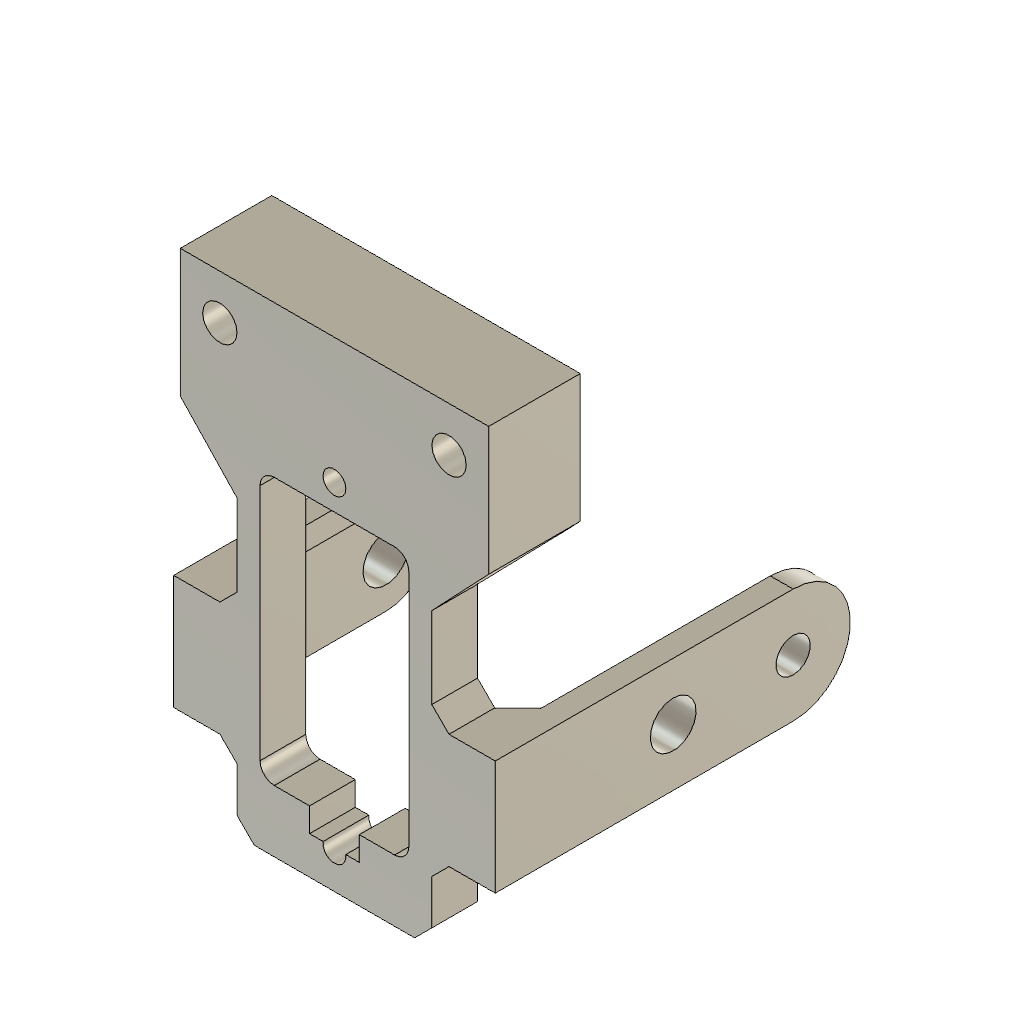
Sub Base native (Autodesk Fusion 360 design; units mm, degrees)
part number: 2026-10-13-22-11-32-808
Autodesk Fusion 360 part; units mm, degrees
ref_plane "WorkPlane1" through (0, -13.5322, 0) normal (0, 1, 0) x (0, 0, 1)
sketch "Back plate" plane through (0, -13.5322, 0) normal (0, 1, 0) x (1, 0, 0)
  line L0 (50.9682, -30.0122) -> (24.0314, -30.0122)
  line L1 (24.0314, -30.0122) -> (24.0314, -18.8374)
  line L2 (24.0314, -18.8374) -> (28.9998, -13.5996)
  line L3 (28.9998, -13.5996) -> (28.9998, -6.5)
  line L4 (28.9998, -6.5) -> (27.4998, -5)
  line L5 (27.4998, -5) -> (23.4588, -5)
  line L6 (23.4588, -5) -> (23.4588, 5)
  line L7 (23.4588, 5) -> (27.4998, 5)
  line L8 (27.4998, 5) -> (28.9998, 6.5)
  line L9 (28.9998, 6.5) -> (28.9998, 10.4007)
  line L10 (28.9998, 10.4007) -> (30.4998, 11.9007)
  line L11 (30.4998, 11.9007) -> (44.4998, 11.9007)
  line L12 (44.4998, 11.9007) -> (45.9998, 10.4007)
  line L13 (45.9998, 10.4007) -> (45.9998, 6.5)
  line L14 (45.9998, 6.5) -> (47.4998, 5)
  line L15 (47.4998, 5) -> (51.5407, 5)
  line L16 (51.5407, 5) -> (51.5407, -5)
  line L17 (51.5407, -5) -> (47.4998, -5)
  line L18 (47.4998, -5) -> (45.9998, -6.5)
  line L19 (45.9998, -6.5) -> (45.9998, -13.5996)
  line L20 (45.9998, -13.5996) -> (50.9682, -18.8374)
  line L21 (50.9682, -18.8374) -> (50.9682, -30.0122)
  dimension "d59" = 50.9682
  dimension "d60" = 30.0122
  dimension "d61" = 24.0314
  dimension "d62" = 18.8374
  dimension "d63" = 28.9998
  dimension "d64" = 13.5996
  dimension "d65" = 6.5
  dimension "d66" = 27.4998
  dimension "d67" = 5
  dimension "d68" = 23.4588
  dimension "d69" = 5
  dimension "d70" = 27.4998
  dimension "d71" = 28.9998
  dimension "d72" = 6.5
  dimension "d73" = 10.4007
  dimension "d74" = 30.4998
  dimension "d75" = 11.9007
  dimension "d76" = 44.4998
  dimension "d77" = 45.9998
  dimension "d78" = 10.4007
  dimension "d79" = 6.5
  dimension "d80" = 47.4998
  dimension "d81" = 5
  dimension "d82" = 51.5407
  dimension "d83" = 5
  dimension "d84" = 47.4998
  dimension "d85" = 45.9998
  dimension "d86" = 6.5
  dimension "d87" = 13.5996
  dimension "d88" = 18.8374
  constraint horizontal L0
  constraint vertical L1
  constraint vertical L3
  constraint horizontal L5
  constraint vertical L6
  constraint horizontal L7
  constraint vertical L9
  constraint horizontal L11
  constraint vertical L13
  constraint horizontal L15
  constraint vertical L16
  constraint horizontal L17
  constraint vertical L19
  constraint vertical L21
  measures "d59" horizontal distance of origin L0.start
  measures "d60" vertical distance of origin L0.start
  measures "d61" horizontal distance of origin L0.end
  measures "d62" vertical distance of origin L1.end
  measures "d63" horizontal distance of origin L2.end
  measures "d64" vertical distance of origin L2.end
  measures "d65" vertical distance of origin L3.end
  measures "d66" horizontal distance of origin L4.end
  measures "d67" vertical distance of origin L4.end
  measures "d68" horizontal distance of origin L5.end
  measures "d69" vertical distance of origin L6.end
  measures "d70" horizontal distance of origin L7.end
  measures "d71" horizontal distance of origin L8.end
  measures "d72" vertical distance of origin L8.end
  measures "d73" vertical distance of origin L9.end
  measures "d74" horizontal distance of origin L10.end
  measures "d75" vertical distance of origin L10.end
  measures "d76" horizontal distance of origin L11.end
  measures "d77" horizontal distance of origin L12.end
  measures "d78" vertical distance of origin L12.end
  measures "d79" vertical distance of origin L13.end
  measures "d80" horizontal distance of origin L14.end
  measures "d81" vertical distance of origin L14.end
  measures "d82" horizontal distance of origin L15.end
  measures "d83" vertical distance of origin L16.end
  measures "d84" horizontal distance of origin L17.end
  measures "d85" horizontal distance of origin L18.end
  measures "d86" vertical distance of origin L18.end
  measures "d87" vertical distance of origin L19.end
  measures "d88" vertical distance of origin L20.end
extrude "Back plate (1)" add sketch "Back plate" along normal mid plane 4
ref_plane "WorkPlane2" through (0, -9.5322, 0) normal (0, 1, 0) x (0, 0, 1)
sketch "Top block" plane through (0, -9.5322, 0) normal (0, 1, 0) x (1, 0, 0)
  line L0 (50.9682, -30.0122) -> (24.0314, -30.0122)
  line L1 (24.0314, -30.0122) -> (24.0314, -18.8374)
  line L2 (24.0314, -18.8374) -> (28.9998, -13.5996)
  line L3 (28.9998, -13.5996) -> (28.9998, -22.1993)
  line L4 (28.9998, -22.1993) -> (45.9998, -22.1993)
  line L5 (45.9998, -22.1993) -> (45.9998, -13.5996)
  line L6 (45.9998, -13.5996) -> (50.9682, -18.8374)
  line L7 (50.9682, -18.8374) -> (50.9682, -30.0122)
  dimension "d89" = 50.9682
  dimension "d90" = 30.0122
  dimension "d91" = 24.0314
  dimension "d92" = 18.8374
  dimension "d93" = 28.9998
  dimension "d94" = 13.5996
  dimension "d95" = 22.1993
  dimension "d96" = 45.9998
  dimension "d97" = 13.5996
  dimension "d98" = 18.8374
  constraint horizontal L0
  constraint vertical L1
  constraint vertical L3
  constraint horizontal L4
  constraint vertical L5
  constraint vertical L7
  measures "d89" horizontal distance of origin L0.start
  measures "d90" vertical distance of origin L0.start
  measures "d91" horizontal distance of origin L0.end
  measures "d92" vertical distance of origin L1.end
  measures "d93" horizontal distance of origin L2.end
  measures "d94" vertical distance of origin L2.end
  measures "d95" vertical distance of origin L3.end
  measures "d96" horizontal distance of origin L4.end
  measures "d97" vertical distance of origin L5.end
  measures "d98" vertical distance of origin L6.end
extrude "Top block (1)" add sketch "Top block" along normal mid plane 4
ref_plane "WorkPlane3" through (0, 0, 17.8995) normal (0, 0, 1) x (1, 0, 0)
sketch "Gusset taper L" plane through (0, 0, 17.8995) normal (0, 0, 1) x (1, 0, 0)
  line L0 (28.9998, -11.5322) -> (24.9998, -7.5322)
  line L1 (24.9998, -7.5322) -> (28.9998, -7.5322)
  line L2 (28.9998, -7.5322) -> (28.9998, -11.5322)
  dimension "d99" = 28.9998
  dimension "d100" = 11.5322
  dimension "d101" = 24.9998
  dimension "d102" = 7.5322
  constraint horizontal L1
  constraint vertical L2
  measures "d99" horizontal distance of origin L0.start
  measures "d100" vertical distance of origin L0.start
  measures "d101" horizontal distance of origin L0.end
  measures "d102" vertical distance of origin L0.end
extrude "Gusset taper L (1)" cut sketch "Gusset taper L" along normal mid plane 8.5997
ref_plane "WorkPlane4" through (0, 0, 17.8995) normal (0, 0, 1) x (1, 0, 0)
sketch "Gusset taper R" plane through (0, 0, 17.8995) normal (0, 0, 1) x (1, 0, 0)
  line L0 (45.9998, -11.5322) -> (45.9998, -7.5322)
  line L1 (45.9998, -7.5322) -> (49.9998, -7.5322)
  line L2 (49.9998, -7.5322) -> (45.9998, -11.5322)
  dimension "d103" = 45.9998
  dimension "d104" = 11.5322
  dimension "d105" = 7.5322
  dimension "d106" = 49.9998
  constraint vertical L0
  constraint horizontal L1
  measures "d103" horizontal distance of origin L0.start
  measures "d104" vertical distance of origin L0.start
  measures "d105" vertical distance of origin L0.end
  measures "d106" horizontal distance of origin L1.end
extrude "Gusset taper R (1)" cut sketch "Gusset taper R" along normal mid plane 8.5997
ref_plane "WorkPlane5" through (24.9588, 0, 0) normal (1, 0, 0) x (0, 1, 0)
sketch "Arm L" plane through (24.9588, 0, 0) normal (1, 0, 0) x (0, 0, -1)
  line L0 (-5, -15.5322) -> (-5, 0)
  arc A0 (5, 0) -> (-5, 0) centre (0, 0) ccw
  line L1 (5, 0) -> (5, -15.5322)
  line L2 (5, -15.5322) -> (-5, -15.5322)
  dimension "d107" = 5
  dimension "d108" = 15.5322
  constraint vertical L0
  constraint vertical L1
  constraint horizontal L2
  constraint tangent L0 A0
  constraint tangent A0 L1
  constraint coincident A0.centre origin
  measures "d107" radius of A0
  measures "d108" vertical distance of A0.centre L0.start
extrude "Arm L (1)" add sketch "Arm L" along normal mid plane 3
ref_plane "WorkPlane6" through (50.0407, 0, 0) normal (1, 0, 0) x (0, 1, 0)
sketch "Arm R" plane through (50.0407, 0, 0) normal (1, 0, 0) x (0, 0, -1)
  line L0 (-5, -15.5322) -> (-5, 10.47)
  arc A0 (5, 10.47) -> (-5, 10.47) centre (0, 10.47) ccw
  line L1 (5, 10.47) -> (5, -15.5322)
  line L2 (5, -15.5322) -> (-5, -15.5322)
  dimension "d109" = 5
  dimension "d110" = 10.47
  dimension "d111" = 15.5322
  constraint vertical L0
  constraint vertical L1
  constraint horizontal L2
  constraint tangent L0 A0
  constraint tangent A0 L1
  constraint vertical origin A0.centre
  measures "d109" radius of A0
  measures "d110" vertical distance of origin A0.centre
  measures "d111" vertical distance of origin L0.start
extrude "Arm R (1)" add sketch "Arm R" along normal mid plane 3
chamfer "Arm L chamfer" distance 1 angle 45 3 edges at (26.4588, -5.7661, -5) (26.4588, 5, 0) (26.4588, -5.7661, 5) tangent chain off
chamfer "Arm R chamfer" distance 1 angle 45 3 edges at (48.5407, -0.5311, 5) (48.5407, 15.47, 0) (48.5407, -0.5311, -5) tangent chain off
sketch "Arm root L" plane through (0, 0, 0) normal (0, 0, 1) x (1, 0, 0)
  line L0 (27.4588, -11.5322) -> (25.4588, -9.5322)
  line L1 (25.4588, -9.5322) -> (25.4588, -11.5322)
  line L2 (25.4588, -11.5322) -> (27.4588, -11.5322)
  dimension "d112" = 27.4588
  dimension "d113" = 11.5322
  dimension "d114" = 25.4588
  dimension "d115" = 9.5322
  constraint vertical L1
  constraint horizontal L2
  measures "d112" horizontal distance of origin L0.start
  measures "d113" vertical distance of origin L0.start
  measures "d114" horizontal distance of origin L0.end
  measures "d115" vertical distance of origin L0.end
extrude "Arm root L (1)" add sketch "Arm root L" along normal mid plane 10
sketch "Arm root R" plane through (0, 0, 0) normal (0, 0, 1) x (1, 0, 0)
  line L0 (47.5407, -11.5322) -> (49.5407, -11.5322)
  line L1 (49.5407, -11.5322) -> (49.5407, -9.5322)
  line L2 (49.5407, -9.5322) -> (47.5407, -11.5322)
  dimension "d116" = 47.5407
  dimension "d117" = 11.5322
  dimension "d118" = 49.5407
  dimension "d119" = 9.5322
  constraint horizontal L0
  constraint vertical L1
  measures "d116" horizontal distance of origin L0.start
  measures "d117" vertical distance of origin L0.start
  measures "d118" horizontal distance of origin L0.end
  measures "d119" vertical distance of origin L1.end
extrude "Arm root R (1)" add sketch "Arm root R" along normal mid plane 10
ref_plane "WorkPlane7" through (24.9588, 0, 0) normal (1, 0, 0) x (0, 1, 0)
sketch "Pivot hole L" plane through (24.9588, 0, 0) normal (1, 0, 0) x (0, 0, -1)
  circle A0 centre (0, 0) radius 2
  dimension "d120" = 4
  constraint coincident A0.centre origin
  measures "d120" diameter of A0
extrude "Pivot hole L (1)" cut sketch "Pivot hole L" along normal mid plane 3
ref_plane "WorkPlane8" through (50.0407, 0, 0) normal (1, 0, 0) x (0, 1, 0)
sketch "Pivot hole R" plane through (50.0407, 0, 0) normal (1, 0, 0) x (0, 0, -1)
  circle A0 centre (0, 0) radius 2
  dimension "d121" = 4
  constraint coincident A0.centre origin
  measures "d121" diameter of A0
extrude "Pivot hole R (1)" cut sketch "Pivot hole R" along normal mid plane 3
ref_plane "WorkPlane9" through (50.0407, 0, 0) normal (1, 0, 0) x (0, 1, 0)
sketch "End hole R" plane through (50.0407, 0, 0) normal (1, 0, 0) x (0, 0, -1)
  circle A0 centre (0, 10.47) radius 1.5
  dimension "d122" = 3
  dimension "d123" = 10.47
  constraint vertical origin A0.centre
  measures "d122" diameter of A0
  measures "d123" vertical distance of origin A0.centre
extrude "End hole R (1)" cut sketch "End hole R" along normal mid plane 3
ref_plane "WorkPlane10" through (0, -13.5322, 0) normal (0, 1, 0) x (0, 0, 1)
sketch "Window" plane through (0, -13.5322, 0) normal (0, 1, 0) x (1, 0, 0)
  line L0 (43.9998, 5.2507) -> (43.9998, -15.5493)
  arc A0 (42.7498, -16.7993) -> (43.9998, -15.5493) centre (42.7498, -15.5493) ccw
  line L1 (42.7498, -16.7993) -> (32.2498, -16.7993)
  arc A1 (30.9998, -15.5493) -> (32.2498, -16.7993) centre (32.2498, -15.5493) ccw
  line L2 (30.9998, -15.5493) -> (30.9998, 5.2507)
  arc A2 (32.2498, 6.5007) -> (30.9998, 5.2507) centre (32.2498, 5.2507) ccw
  line L3 (32.2498, 6.5007) -> (35.3266, 6.5007)
  line L4 (35.3266, 6.5007) -> (35.3266, 8.6007)
  line L5 (35.3266, 8.6007) -> (36.5111, 8.6007)
  arc A3 (38.4885, 8.6007) -> (36.5111, 8.6007) centre (37.4998, 8.7507) ccw
  line L6 (38.4885, 8.6007) -> (39.673, 8.6007)
  line L7 (39.673, 8.6007) -> (39.673, 6.5007)
  line L8 (39.673, 6.5007) -> (42.7498, 6.5007)
  arc A4 (43.9998, 5.2507) -> (42.7498, 6.5007) centre (42.7498, 5.2507) ccw
  dimension "d124" = 1.25
  dimension "d125" = 1
  dimension "d126" = 42.7498
  dimension "d127" = 15.5493
  dimension "d128" = 32.2498
  dimension "d129" = 5.2507
  dimension "d130" = 37.4998
  dimension "d131" = 8.7507
  dimension "d132" = 5.2507
  dimension "d133" = 35.3266
  dimension "d134" = 8.6007
  dimension "d135" = 38.4885
  dimension "d136" = 39.673
  constraint vertical L0
  constraint horizontal L1
  constraint vertical L2
  constraint horizontal L3
  constraint vertical L4
  constraint horizontal L5
  constraint horizontal L6
  constraint vertical L7
  constraint horizontal L8
  constraint tangent L0 A4
  constraint tangent L0 A0
  constraint tangent A0 L1
  constraint tangent L1 A1
  constraint tangent A1 L2
  constraint tangent L2 A2
  constraint tangent A2 L3
  constraint tangent L8 A4
  constraint equal A0 A1
  constraint equal A0 A2
  constraint equal A0 A4
  measures "d124" radius of A0
  measures "d125" radius of A3
  measures "d126" horizontal distance of origin A0.centre
  measures "d127" vertical distance of origin A0.centre
  measures "d128" horizontal distance of origin A1.centre
  measures "d129" vertical distance of origin A2.centre
  measures "d130" horizontal distance of origin A3.centre
  measures "d131" vertical distance of origin A3.centre
  measures "d132" vertical distance of origin A4.centre
  measures "d133" horizontal distance of origin L3.end
  measures "d134" vertical distance of origin L4.end
  measures "d135" horizontal distance of origin A3.start
  measures "d136" horizontal distance of origin L6.end
extrude "Window (1)" cut sketch "Window" along normal mid plane 4
ref_plane "WorkPlane11" through (0, -11.5322, 0) normal (0, 1, 0) x (0, 0, 1)
sketch "Top hole L" plane through (0, -11.5322, 0) normal (0, 1, 0) x (1, 0, 0)
  circle A0 centre (27.4936, -26.1058) radius 1.5
  dimension "d137" = 3
  dimension "d138" = 27.4936
  dimension "d139" = 26.1058
  measures "d137" diameter of A0
  measures "d138" horizontal distance of origin A0.centre
  measures "d139" vertical distance of origin A0.centre
extrude "Top hole L (1)" cut sketch "Top hole L" along normal mid plane 8
ref_plane "WorkPlane12" through (0, -11.5322, 0) normal (0, 1, 0) x (0, 0, 1)
sketch "Top hole R" plane through (0, -11.5322, 0) normal (0, 1, 0) x (1, 0, 0)
  circle A0 centre (47.5059, -26.1058) radius 1.5
  dimension "d140" = 3
  dimension "d141" = 47.5059
  dimension "d142" = 26.1058
  measures "d140" diameter of A0
  measures "d141" horizontal distance of origin A0.centre
  measures "d142" vertical distance of origin A0.centre
extrude "Top hole R (1)" cut sketch "Top hole R" along normal mid plane 8
ref_plane "WorkPlane13" through (0, -13.5322, 0) normal (0, 1, 0) x (0, 0, 1)
sketch "Centre hole" plane through (0, -13.5322, 0) normal (0, 1, 0) x (1, 0, 0)
  circle A0 centre (37.4998, -19.0493) radius 1
  dimension "d143" = 2
  dimension "d144" = 37.4998
  dimension "d145" = 19.0493
  measures "d143" diameter of A0
  measures "d144" horizontal distance of origin A0.centre
  measures "d145" vertical distance of origin A0.centre
extrude "Centre hole (1)" cut sketch "Centre hole" along normal mid plane 4
named bodies: "Sub Base native"
